Autodesk Fusion 360 part; units mm, degrees
(part 5 of 18)
  line L2716 (109.469, -153.766) -> (109.882, -153.353)
  line L2717 (144.42, -71.6049) -> (143.99, -72.0008)
  line L2718 (107.344, -63.166) -> (107.232, -63.7491)
  line L2719 (123.304, -154.504) -> (123.641, -154.981)
  line L2720 (34.8557, -118.401) -> (35.2286, -117.939)
  line L2721 (35.2286, -117.939) -> (35.57, -117.453)
  line L2722 (19.3443, -86.866) -> (19.232, -87.4491)
  line L2723 (69.1318, -73.6069) -> (69.6987, -73.7835)
  line L2724 (37.0318, -88.85) -> (37.0121, -88.2565)
  line L2725 (19.7392, -92.1175) -> (19.9741, -92.6629)
  line L2726 (71.4521, -74.0832) -> (72.0455, -74.1049)
  line L2727 (36.9725, -89.8793) -> (37.0211, -89.2874)
  line L2728 (19.1297, -89.225) -> (19.1742, -89.8171)
  line L2729 (65.8816, -58.5528) -> (66.3203, -58.1668)
  line L2730 (63.3803, -67.2861) -> (63.541, -67.8577)
  line L2731 (80.6591, -62.2784) -> (80.8266, -62.8382)
  line L2732 (19.495, -86.2917) -> (19.3443, -86.866)
  line L2733 (63.1589, -63.6096) -> (63.2769, -63.0373)
  line L2734 (23.5183, -96.5579) -> (24.0392, -96.8431)
  line L2735 (66.3203, -58.1668) -> (66.7829, -57.8099)
  line L2736 (63.078, -64.1883) -> (63.1589, -63.6096)
  line L2737 (37.0121, -88.2565) -> (36.9531, -87.6656)
  line L2738 (69.2202, -73.7373) -> (68.672, -73.5351)
  line L2739 (63.2769, -63.0373) -> (63.4315, -62.4738)
  line L2740 (24.5778, -97.0931) -> (25.1318, -97.3069)
  line L2741 (64.7274, -59.869) -> (65.0836, -59.4057)
  line L2742 (23.0175, -96.2389) -> (23.5183, -96.5579)
  line L2743 (70.35, -74.0337) -> (69.7803, -73.9038)
  line L2744 (76.5607, -73.0111) -> (76.0441, -73.2841)
  line L2745 (19.6834, -85.7285) -> (19.495, -86.2917)
  line L2746 (76.1995, -57.0936) -> (76.7108, -57.3764)
  line L2747 (78.8234, -71.1821) -> (78.42, -71.6049)
  line L2748 (72.6766, -74.1801) -> (72.0926, -74.2)
  line L2749 (64.3113, -69.7975) -> (64.0276, -69.2867)
  line L2750 (67.5183, -72.8579) -> (68.0392, -73.1431)
  line L2751 (36.7185, -86.5021) -> (36.5439, -85.9345)
  line L2752 (80.6024, -68.1858) -> (80.3887, -68.7297)
  line L2753 (20.8876, -94.1892) -> (21.2572, -94.6539)
  line L2754 (36.5439, -85.9345) -> (36.3321, -85.3798)
  line L2755 (33.0844, -96.274) -> (33.5654, -95.9258)
  line L2756 (30.3945, -97.4999) -> (30.9627, -97.3272)
  line L2757 (65.0836, -59.4057) -> (65.4688, -58.9664)
  line L2758 (19.3817, -91.3597) -> (19.2379, -90.7934)
  line L2759 (35.2286, -94.2393) -> (35.57, -93.7534)
  line L2760 (23.3845, -81.2228) -> (22.8893, -81.5505)
  line L2761 (79.8585, -69.7704) -> (79.5441, -70.263)
  line L2762 (25.5484, -80.2593) -> (24.9847, -80.4458)
  line L2763 (25.1318, -97.3069) -> (25.6987, -97.4835)
  line L2764 (81.0514, -63.9844) -> (81.1079, -64.566)
  line L2765 (81.1251, -65.3237) -> (81.0951, -65.9073)
  line L2766 (22.8893, -81.5505) -> (22.417, -81.9104)
  line L2767 (80.7806, -67.6293) -> (80.6024, -68.1858)
  line L2768 (68.138, -73.2979) -> (67.6204, -73.0267)
  line L2769 (68.8336, -56.7011) -> (69.3856, -56.5094)
  line L2770 (67.1214, -72.7227) -> (66.643, -72.3871)
  line L2771 (64.402, -60.3542) -> (64.7274, -59.869)
  line L2772 (63.7774, -68.7587) -> (63.5618, -68.2156)
  line L2773 (64.9746, -70.759) -> (64.6274, -70.289)
  line L2774 (63.1742, -66.1171) -> (63.2578, -66.705)
  line L2775 (64.0276, -69.2867) -> (63.7774, -68.7587)
  line L2776 (69.9488, -56.3538) -> (70.5208, -56.2348)
  line L2777 (63.3817, -67.6597) -> (63.2379, -67.0934)
  line L2778 (80.3887, -68.7297) -> (80.1404, -69.2586)
  line L2779 (20.17, -84.6459) -> (19.9088, -85.1791)
  line L2780 (79.3045, -59.7036) -> (79.6409, -60.1813)
  line L2781 (26.2761, -97.6221) -> (26.8615, -97.7221)
  line L2782 (32.0585, -96.8711) -> (32.5813, -96.5896)
  line L2783 (32.5813, -96.5896) -> (33.0844, -96.274)
  line L2784 (27.8893, -79.897) -> (27.2963, -79.9291)
  line L2785 (80.8266, -62.8382) -> (80.9575, -63.4077)
  line L2786 (21.9695, -82.3007) -> (21.5489, -82.7199)
  line L2787 (72.2663, -56.102) -> (72.8498, -56.1331)
  line L2788 (63.9741, -68.9629) -> (64.2446, -69.4915)
  line L2789 (19.2379, -90.7934) -> (19.1309, -90.2189)
  line L2790 (20.6274, -93.989) -> (20.3113, -93.4975)
  line L2791 (19.0332, -88.6312) -> (19.0347, -88.471)
  line L2792 (66.7829, -57.8099) -> (67.2676, -57.4835)
  line L2793 (79.1986, -70.7342) -> (78.8234, -71.1821)
  line L2794 (19.2578, -90.405) -> (19.3803, -90.9861)
  line L2795 (65.6569, -71.3931) -> (66.0847, -71.8049)
  line L2796 (36.5935, -91.6172) -> (36.7582, -91.0467)
  line L2797 (19.0291, -89.0553) -> (19.0332, -88.6312)
  line L2798 (31.9179, -80.7606) -> (31.3734, -80.5239)
  line L2799 (65.4688, -58.9664) -> (65.8816, -58.5528)
  line L2800 (33.9045, -82.0507) -> (33.4411, -81.6795)
  line L2801 (68.2951, -56.928) -> (68.8336, -56.7011)
  line L2802 (27.4521, -97.7832) -> (28.0455, -97.8049)
  line L2803 (72.0455, -74.1049) -> (72.6391, -74.0873)
  line L2804 (36.8551, -87.08) -> (36.7185, -86.5021)
  line L2805 (71.5085, -74.1821) -> (70.9269, -74.1266)
  line L2806 (77.9903, -72.0008) -> (77.5358, -72.3681)
  line L2807 (22.417, -81.9104) -> (21.9695, -82.3007)
  line L2808 (34.7525, -82.8812) -> (34.3423, -82.4519)
  line L2809 (69.3856, -56.5094) -> (69.9488, -56.3538)
  line L2810 (63.1309, -66.5189) -> (63.0612, -65.9388)
  line L2811 (73.4301, -56.2018) -> (74.0047, -56.3077)
  line L2812 (20.0276, -92.9867) -> (19.7774, -92.4587)
  line L2813 (19.1742, -89.8171) -> (19.2578, -90.405)
  line L2814 (20.5495, -93.701) -> (20.8876, -94.1892)
  line L2815 (19.3803, -90.9861) -> (19.541, -91.5577)
  line L2816 (73.2581, -74.1226) -> (72.6766, -74.1801)
  line L2817 (36.9531, -87.6656) -> (36.8551, -87.08)
  line L2818 (63.2578, -66.705) -> (63.3803, -67.2861)
  line L2819 (21.5489, -82.7199) -> (21.157, -83.166)
  line L2820 (37.0211, -89.2874) -> (37.0318, -88.85)
  line L2821 (80.4559, -61.7305) -> (80.6591, -62.2784)
  line L2822 (75.5109, -73.5231) -> (74.9634, -73.7273)
  line L2823 (77.6734, -58.038) -> (78.1207, -58.414)
  line L2824 (34.3423, -82.4519) -> (33.9045, -82.0507)
  line L2825 (31.3734, -80.5239) -> (30.8143, -80.3237)
  line L2826 (32.4456, -81.033) -> (31.9179, -80.7606)
  line L2827 (22.539, -95.8873) -> (23.0175, -96.2389)
  line L2828 (29.075, -79.9508) -> (28.483, -79.9042)
  line L2829 (77.5358, -72.3681) -> (77.0587, -72.7054)
  line L2830 (63.0612, -65.9388) -> (63.0291, -65.3553)
  line L2831 (35.8785, -93.246) -> (36.1527, -92.7193)
  line L2832 (69.6987, -73.7835) -> (70.2761, -73.9221)
  line L2833 (63.6222, -61.9215) -> (63.8482, -61.3827)
  line L2834 (29.2302, -97.7304) -> (29.8162, -97.6345)
  line L2835 (26.7068, -80.0004) -> (26.1233, -80.1107)
  line L2836 (36.3321, -85.3798) -> (36.084, -84.8403)
  line L2837 (35.1334, -83.3368) -> (34.7525, -82.8812)
  line L2838 (64.6274, -70.289) -> (64.3113, -69.7975)
  line L2839 (66.0847, -71.8049) -> (66.539, -72.1873)
  line L2840 (74.0047, -56.3077) -> (74.5713, -56.4506)
  line L2841 (66.1873, -72.0214) -> (65.7561, -71.627)
  line L2842 (36.8847, -90.4665) -> (36.9725, -89.8793)
  line L2843 (80.9575, -63.4077) -> (81.0514, -63.9844)
  line L2844 (79.6409, -60.1813) -> (79.9457, -60.6798)
  line L2845 (67.6204, -73.0267) -> (67.1214, -72.7227)
  line L2846 (23.9003, -80.9286) -> (23.3845, -81.2228)
  line L2847 (36.3914, -92.1756) -> (36.5935, -91.6172)
  line L2848 (64.5495, -70.001) -> (64.8876, -70.4892)
  line L2849 (71.682, -56.1086) -> (72.2663, -56.102)
  line L2850 (78.5428, -58.818) -> (78.9379, -59.2485)
  line L2851 (66.643, -72.3871) -> (66.1873, -72.0214)
  line L2852 (33.4411, -81.6795) -> (32.954, -81.3397)
  line L2853 (19.9741, -92.6629) -> (20.2446, -93.1915)
  line L2854 (74.4039, -73.8957) -> (73.8346, -74.0276)
  line L2855 (36.1527, -92.7193) -> (36.3914, -92.1756)
  line L2856 (28.6391, -97.7873) -> (29.2302, -97.7304)
  line L2857 (74.5713, -56.4506) -> (75.1275, -56.6297)
  line L2858 (19.0612, -89.6388) -> (19.0291, -89.0553)
  line L2859 (72.8498, -56.1331) -> (73.4301, -56.2018)
  line L2860 (32.954, -81.3397) -> (32.4456, -81.033)
  line L2861 (73.8346, -74.0276) -> (73.2581, -74.1226)
  line L2862 (70.9269, -74.1266) -> (70.35, -74.0337)
  line L2863 (35.57, -93.7534) -> (35.8785, -93.246)
  line L2864 (71.0994, -56.1529) -> (71.682, -56.1086)
  line L2865 (63.5618, -68.2156) -> (63.3817, -67.6597)
  line L2866 (20.3113, -93.4975) -> (20.0276, -92.9867)
  line L2867 (69.7803, -73.9038) -> (69.2202, -73.7373)
  line L2868 (19.7774, -92.4587) -> (19.5618, -91.9156)
  line L2869 (19.232, -87.4491) -> (19.1587, -88.0384)
  line L2870 (30.8143, -80.3237) -> (30.2432, -80.161)
  line L2871 (65.7561, -71.627) -> (65.3513, -71.2056)
  line L2872 (80.9224, -67.0625) -> (80.7806, -67.6293)
  line L2873 (81.1079, -64.566) -> (81.1268, -65.15)
  line L2874 (63.0347, -64.771) -> (63.078, -64.1883)
  line L2875 (24.0392, -96.8431) -> (24.5778, -97.0931)
  line L2876 (75.1275, -56.6297) -> (75.671, -56.8443)
  line L2877 (35.8006, -84.3185) -> (35.4833, -83.8165)
  line L2878 (26.1233, -80.1107) -> (25.5484, -80.2593)
  line L2879 (19.541, -91.5577) -> (19.7392, -92.1175)
  line L2880 (79.9457, -60.6798) -> (80.2178, -61.1969)
  line L2881 (29.8162, -97.6345) -> (30.3945, -97.4999)
  line L2882 (36.084, -84.8403) -> (35.8006, -84.3185)
  line L2883 (35.4833, -83.8165) -> (35.1334, -83.3368)
  line L2884 (68.5778, -73.3931) -> (69.1318, -73.6069)
  line L2885 (81.1268, -65.15) -> (81.1251, -65.3237)
  line L2886 (63.0291, -65.3553) -> (63.0332, -64.9312)
  line L2887 (19.1245, -88.6312) -> (19.1297, -89.225)
  line L2888 (78.1207, -58.414) -> (78.5428, -58.818)
  line L2889 (28.483, -79.9042) -> (27.8893, -79.897)
  line L2890 (19.1587, -88.0384) -> (19.1245, -88.6312)
  line L2891 (80.2178, -61.1969) -> (80.4559, -61.7305)
  line L2892 (72.0926, -74.2) -> (71.5085, -74.1821)
  line L2893 (67.7724, -57.1892) -> (68.2951, -56.928)
  line L2894 (64.2446, -69.4915) -> (64.5495, -70.001)
  line L2895 (24.9847, -80.4458) -> (24.4345, -80.6692)
  line L2896 (25.6987, -97.4835) -> (26.2761, -97.6221)
  line L2897 (63.8482, -61.3827) -> (64.1085, -60.8595)
  line L2898 (70.8615, -74.0221) -> (71.4521, -74.0832)
  line L2899 (65.2572, -70.9539) -> (65.6569, -71.3931)
  line L2900 (65.3513, -71.2056) -> (64.9746, -70.759)
  line L2901 (24.4345, -80.6692) -> (23.9003, -80.9286)
  line L2902 (78.9379, -59.2485) -> (79.3045, -59.7036)
  line L2903 (29.6626, -80.0365) -> (29.075, -79.9508)
  line L2904 (68.0392, -73.1431) -> (68.5778, -73.3931)
  line L2905 (77.2028, -57.6917) -> (77.6734, -58.038)
  line L2906 (81.0951, -65.9073) -> (81.0274, -66.4877)
  line L2907 (28.0455, -97.8049) -> (28.6391, -97.7873)
  line L2908 (74.9634, -73.7273) -> (74.4039, -73.8957)
  line L2909 (64.1085, -60.8595) -> (64.402, -60.3542)
  line L2910 (19.0347, -88.471) -> (19.078, -87.8883)
  line L2911 (66.539, -72.1873) -> (67.0175, -72.5389)
  line L2912 (27.2963, -79.9291) -> (26.7068, -80.0004)
  line L2913 (22.0847, -95.5049) -> (22.539, -95.8873)
  line L2914 (20.7955, -83.6371) -> (20.466, -84.1311)
  line L2915 (34.0223, -95.5465) -> (34.453, -95.1378)
  line L2916 (68.672, -73.5351) -> (68.138, -73.2979)
  line L2917 (67.2676, -57.4835) -> (67.7724, -57.1892)
  line L2918 (63.2379, -67.0934) -> (63.1309, -66.5189)
  line L2919 (63.4315, -62.4738) -> (63.6222, -61.9215)
  line L2920 (63.7392, -68.4175) -> (63.9741, -68.9629)
  line L2921 (63.541, -67.8577) -> (63.7392, -68.4175)
  line L2922 (67.0175, -72.5389) -> (67.5183, -72.8579)
  line L2923 (64.8876, -70.4892) -> (65.2572, -70.9539)
  line L2924 (34.453, -95.1378) -> (34.8557, -94.7014)
  line L2925 (19.5618, -91.9156) -> (19.3817, -91.3597)
  line L2926 (70.2761, -73.9221) -> (70.8615, -74.0221)
  line L2927 (78.42, -71.6049) -> (77.9903, -72.0008)
  line L2928 (34.8557, -94.7014) -> (35.2286, -94.2393)
  line L2929 (79.5441, -70.263) -> (79.1986, -70.7342)
  line L2930 (36.7582, -91.0467) -> (36.8847, -90.4665)
  line L2931 (26.8615, -97.7221) -> (27.4521, -97.7832)
  line L2932 (21.6569, -95.0931) -> (22.0847, -95.5049)
  line L2933 (21.2572, -94.6539) -> (21.6569, -95.0931)
  line L2934 (76.7108, -57.3764) -> (77.2028, -57.6917)
  line L2935 (30.9627, -97.3272) -> (31.5182, -97.1173)
  line L2936 (75.671, -56.8443) -> (76.1995, -57.0936)
  line L2937 (30.2432, -80.161) -> (29.6626, -80.0365)
  line L2938 (19.1309, -90.2189) -> (19.0612, -89.6388)
  line L2939 (63.0332, -64.9312) -> (63.0347, -64.771)
  line L2940 (20.2446, -93.1915) -> (20.5495, -93.701)
  line L2941 (20.466, -84.1311) -> (20.17, -84.6459)
  line L2942 (20.9746, -94.459) -> (20.6274, -93.989)
  line L2943 (70.5208, -56.2348) -> (71.0994, -56.1529)
  line L2944 (81.0274, -66.4877) -> (80.9224, -67.0625)
  line L2945 (76.0441, -73.2841) -> (75.5109, -73.5231)
  line L2946 (33.5654, -95.9258) -> (34.0223, -95.5465)
  line L2947 (19.9088, -85.1791) -> (19.6834, -85.7285)
  line L2948 (31.5182, -97.1173) -> (32.0585, -96.8711)
  line L2949 (21.157, -83.166) -> (20.7955, -83.6371)
  line L2950 (80.1404, -69.2586) -> (79.8585, -69.7704)
  line L2951 (77.0587, -72.7054) -> (76.5607, -73.0111)
  line L2952 (191.027, -66.4877) -> (190.922, -67.0625)
  line L2953 (190.922, -67.0625) -> (190.781, -67.6293)
  line L2954 (191.125, -65.3237) -> (191.095, -65.9073)
  line L2955 (153.257, -70.9539) -> (153.657, -71.3931)
  line L2956 (154.539, -72.1873) -> (155.018, -72.5389)
  line L2957 (154.085, -71.8049) -> (154.539, -72.1873)
  line L2958 (155.518, -72.8579) -> (156.039, -73.1431)
  line L2959 (173.131, -66.5189) -> (173.061, -65.9388)
  line L2960 (173.061, -65.9388) -> (173.029, -65.3553)
  line L2961 (173.909, -61.4791) -> (173.683, -62.0285)
  line L2962 (173.344, -63.166) -> (173.232, -63.7491)
  line L2963 (173.495, -62.5917) -> (173.344, -63.166)
  line L2964 (173.13, -65.525) -> (173.174, -66.1171)
  line L2965 (173.232, -63.7491) -> (173.159, -64.3384)
  line L2966 (173.159, -64.3384) -> (173.124, -64.9312)
  line L2967 (151.258, -66.705) -> (151.38, -67.2861)
  line L2968 (151.739, -68.4175) -> (151.974, -68.9629)
  line L2969 (151.541, -67.8577) -> (151.739, -68.4175)
  line L2970 (152.245, -69.4915) -> (152.55, -70.001)
  line L2971 (173.124, -64.9312) -> (173.13, -65.525)
  line L2972 (151.078, -64.1883) -> (151.159, -63.6096)
  line L2973 (151.159, -63.6096) -> (151.277, -63.0373)
  line L2974 (151.432, -62.4738) -> (151.622, -61.9215)
  line L2975 (161.075, -56.2508) -> (160.483, -56.2042)
  line L2976 (163.918, -57.0606) -> (163.373, -56.8239)
  line L2977 (63.9088, -61.4791) -> (63.6834, -62.0285)
  line L2978 (162.814, -56.6237) -> (162.243, -56.461)
  line L2979 (163.373, -56.8239) -> (162.814, -56.6237)
  line L2980 (161.663, -56.3365) -> (161.075, -56.2508)
  line L2981 (176.417, -58.2104) -> (175.97, -58.6007)
  line L2982 (80.8847, -66.7665) -> (80.9725, -66.1793)
  line L2983 (63.6834, -62.0285) -> (63.495, -62.5917)
  line L2984 (64.466, -60.4311) -> (64.17, -60.9459)
  line L2985 (80.9725, -66.1793) -> (81.0211, -65.5875)
  line L2986 (191.095, -65.9073) -> (191.027, -66.4877)
  line L2987 (79.1334, -59.6368) -> (78.7525, -59.1812)
  line L2988 (191.108, -64.566) -> (191.127, -65.15)
  line L2989 (173.238, -67.0934) -> (173.131, -66.5189)
  line L2990 (173.382, -67.6597) -> (173.238, -67.0934)
  line L2991 (191.127, -65.15) -> (191.125, -65.3237)
  line L2992 (190.957, -63.4077) -> (191.051, -63.9844)
  line L2993 (191.051, -63.9844) -> (191.108, -64.566)
  line L2994 (151.974, -68.9629) -> (152.245, -69.4915)
  line L2995 (152.888, -70.4892) -> (153.257, -70.9539)
  line L2996 (152.55, -70.001) -> (152.888, -70.4892)
  line L2997 (153.657, -71.3931) -> (154.085, -71.8049)
  line L2998 (173.777, -68.7587) -> (173.562, -68.2156)
  line L2999 (173.562, -68.2156) -> (173.382, -67.6597)
  line L3000 (176.889, -57.8505) -> (176.417, -58.2104)
  line L3001 (175.549, -59.0199) -> (175.157, -59.466)
  line L3002 (175.97, -58.6007) -> (175.549, -59.0199)
  line L3003 (174.17, -60.9459) -> (173.909, -61.4791)
  line L3004 (175.157, -59.466) -> (174.795, -59.9371)
  line L3005 (174.795, -59.9371) -> (174.466, -60.4311)
  line L3006 (151.382, -67.6597) -> (151.238, -67.0934)
  line L3007 (151.061, -65.9388) -> (151.029, -65.3553)
  line L3008 (151.131, -66.5189) -> (151.061, -65.9388)
  line L3009 (151.033, -64.9312) -> (151.035, -64.771)
  line L3010 (174.466, -60.4311) -> (174.17, -60.9459)
  line L3011 (151.277, -63.0373) -> (151.432, -62.4738)
  line L3012 (173.683, -62.0285) -> (173.495, -62.5917)
  line L3013 (151.848, -61.3827) -> (152.108, -60.8595)
  line L3014 (164.954, -57.6397) -> (164.446, -57.333)
  line L3015 (165.441, -57.9794) -> (164.954, -57.6397)
  line L3016 (64.17, -60.9459) -> (63.9088, -61.4791)
  line L3017 (164.446, -57.333) -> (163.918, -57.0606)
  line L3018 (166.753, -59.1812) -> (166.342, -58.7519)
  line L3019 (162.243, -56.461) -> (161.663, -56.3365)
  line L3020 (182.483, -56.2042) -> (181.889, -56.197)
  line L3021 (80.5935, -67.9172) -> (80.7582, -67.3467)
  line L3022 (65.157, -59.466) -> (64.7955, -59.9371)
  line L3023 (64.7955, -59.9371) -> (64.466, -60.4311)
  line L3024 (80.7582, -67.3467) -> (80.8847, -66.7665)
  line L3025 (190.659, -62.2784) -> (190.827, -62.8382)
  line L3026 (80.084, -61.1403) -> (79.8006, -60.6185)
  line L3027 (190.827, -62.8382) -> (190.957, -63.4077)
  line L3028 (174.028, -69.2867) -> (173.777, -68.7587)
  line L3029 (174.311, -69.7975) -> (174.028, -69.2867)
  line L3030 (190.218, -61.1969) -> (190.456, -61.7305)
  line L3031 (190.456, -61.7305) -> (190.659, -62.2784)
  line L3032 (189.641, -60.1813) -> (189.946, -60.6798)
  line L3033 (151.029, -65.3553) -> (151.033, -64.9312)
  line L3034 (151.174, -66.1171) -> (151.258, -66.705)
  line L3035 (151.035, -64.771) -> (151.078, -64.1883)
  line L3036 (151.38, -67.2861) -> (151.541, -67.8577)
  line L3037 (174.975, -70.759) -> (174.627, -70.289)
  line L3038 (174.627, -70.289) -> (174.311, -69.7975)
  line L3039 (180.707, -56.3004) -> (180.123, -56.4107)
  line L3040 (181.296, -56.2291) -> (180.707, -56.3004)
  line L3041 (179.548, -56.5593) -> (178.985, -56.7458)
  line L3042 (178.985, -56.7458) -> (178.434, -56.9692)
  line L3043 (178.434, -56.9692) -> (177.9, -57.2286)
  line L3044 (180.123, -56.4107) -> (179.548, -56.5593)
  line L3045 (153.756, -71.627) -> (153.351, -71.2056)
  line L3046 (152.627, -70.289) -> (152.311, -69.7975)
  line L3047 (152.975, -70.759) -> (152.627, -70.289)
  line L3048 (152.028, -69.2867) -> (151.777, -68.7587)
  line L3049 (177.385, -57.5228) -> (176.889, -57.8505)
  line L3050 (151.622, -61.9215) -> (151.848, -61.3827)
  line L3051 (177.9, -57.2286) -> (177.385, -57.5228)
  line L3052 (152.402, -60.3542) -> (152.727, -59.869)
  line L3053 (166.342, -58.7519) -> (165.904, -58.3507)
  line L3054 (168.084, -61.1403) -> (167.801, -60.6185)
  line L3055 (65.9695, -58.6007) -> (65.5489, -59.0199)
  line L3056 (167.483, -60.1165) -> (167.133, -59.6368)
  line L3057 (167.801, -60.6185) -> (167.483, -60.1165)
  line L3058 (165.904, -58.3507) -> (165.441, -57.9794)
  line L3059 (186.446, -57.333) -> (185.918, -57.0606)
  line L3060 (80.1527, -69.0193) -> (80.3914, -68.4756)
  line L3061 (65.5489, -59.0199) -> (65.157, -59.466)
  line L3062 (66.8893, -57.8505) -> (66.417, -58.2104)
  line L3063 (80.3914, -68.4756) -> (80.5935, -67.9172)
  line L3064 (189.946, -60.6798) -> (190.218, -61.1969)
  line L3065 (79.8006, -60.6185) -> (79.4833, -60.1165)
  line L3066 (188.938, -59.2485) -> (189.304, -59.7036)
  line L3067 (175.351, -71.2056) -> (174.975, -70.759)
  line L3068 (175.756, -71.627) -> (175.351, -71.2056)
  line L3069 (189.304, -59.7036) -> (189.641, -60.1813)
  line L3070 (188.121, -58.414) -> (188.543, -58.818)
  line L3071 (188.543, -58.818) -> (188.938, -59.2485)
  line L3072 (152.311, -69.7975) -> (152.028, -69.2867)
  line L3073 (151.562, -68.2156) -> (151.382, -67.6597)
  line L3074 (151.777, -68.7587) -> (151.562, -68.2156)
  line L3075 (151.238, -67.0934) -> (151.131, -66.5189)
  line L3076 (176.643, -72.3871) -> (176.187, -72.0214)
  line L3077 (176.187, -72.0214) -> (175.756, -71.627)
  line L3078 (186.954, -57.6397) -> (186.446, -57.333)
  line L3079 (185.373, -56.8239) -> (184.814, -56.6237)
  line L3080 (185.918, -57.0606) -> (185.373, -56.8239)
  line L3081 (183.075, -56.2508) -> (182.483, -56.2042)
  line L3082 (184.814, -56.6237) -> (184.243, -56.461)
  line L3083 (184.243, -56.461) -> (183.663, -56.3365)
  line L3084 (157.78, -73.9038) -> (157.22, -73.7373)
  line L3085 (156.138, -73.2979) -> (155.62, -73.0267)
  line L3086 (156.672, -73.5351) -> (156.138, -73.2979)
  line L3087 (155.121, -72.7227) -> (154.643, -72.3871)
  line L3088 (183.663, -56.3365) -> (183.075, -56.2508)
  line L3089 (152.108, -60.8595) -> (152.402, -60.3542)
  line L3090 (181.889, -56.197) -> (181.296, -56.2291)
  line L3091 (153.084, -59.4057) -> (153.469, -58.9664)
  line L3092 (168.544, -62.2345) -> (168.332, -61.6798)
  line L3093 (168.719, -62.8021) -> (168.544, -62.2345)
  line L3094 (66.417, -58.2104) -> (65.9695, -58.6007)
  line L3095 (168.332, -61.6798) -> (168.084, -61.1403)
  line L3096 (169.012, -64.5565) -> (168.953, -63.9656)
  line L3097 (167.133, -59.6368) -> (166.753, -59.1812)
  line L3098 (190.544, -62.2345) -> (190.332, -61.6798)
  line L3099 (79.57, -70.0534) -> (79.8785, -69.546)
  line L3100 (67.9003, -57.2286) -> (67.3845, -57.5228)
  line L3101 (67.3845, -57.5228) -> (66.8893, -57.8505)
  line L3102 (79.8785, -69.546) -> (80.1527, -69.0193)
  line L3103 (187.203, -57.6917) -> (187.673, -58.038)
  line L3104 (80.5439, -62.2345) -> (80.3321, -61.6798)
  line L3105 (187.673, -58.038) -> (188.121, -58.414)
  line L3106 (177.121, -72.7227) -> (176.643, -72.3871)
  line L3107 (177.62, -73.0267) -> (177.121, -72.7227)
  line L3108 (186.199, -57.0936) -> (186.711, -57.3764)
  line L3109 (186.711, -57.3764) -> (187.203, -57.6917)
  line L3110 (185.128, -56.6297) -> (185.671, -56.8443)
  line L3111 (155.62, -73.0267) -> (155.121, -72.7227)
  line L3112 (154.187, -72.0214) -> (153.756, -71.627)
  line L3113 (154.643, -72.3871) -> (154.187, -72.0214)
  line L3114 (153.351, -71.2056) -> (152.975, -70.759)
  line L3115 (178.672, -73.5351) -> (178.138, -73.2979)
  line L3116 (178.138, -73.2979) -> (177.62, -73.0267)
  line L3117 (189.801, -60.6185) -> (189.483, -60.1165)
  line L3118 (190.084, -61.1403) -> (189.801, -60.6185)
  line L3119 (189.133, -59.6368) -> (188.753, -59.1812)
  line L3120 (188.753, -59.1812) -> (188.342, -58.7519)
  line L3121 (188.342, -58.7519) -> (187.904, -58.3507)
  line L3122 (189.483, -60.1165) -> (189.133, -59.6368)
  line L3123 (162.404, -73.8957) -> (161.835, -74.0276)
  line L3124 (160.677, -74.1801) -> (160.093, -74.2)
  line L3125 (161.258, -74.1226) -> (160.677, -74.1801)
  line L3126 (159.509, -74.1821) -> (158.927, -74.1266)
  line L3127 (187.441, -57.9794) -> (186.954, -57.6397)
  line L3128 (152.727, -59.869) -> (153.084, -59.4057)
  line L3129 (187.904, -58.3507) -> (187.441, -57.9794)
  line L3130 (153.882, -58.5528) -> (154.32, -58.1668)
  line L3131 (168.953, -63.9656) -> (168.855, -63.38)
  line L3132 (168.885, -66.7665) -> (168.972, -66.1793)
  line L3133 (68.9847, -56.7458) -> (68.4345, -56.9692)
  line L3134 (169.021, -65.5875) -> (169.032, -65.15)
  line L3135 (168.972, -66.1793) -> (169.021, -65.5875)
  line L3136 (168.855, -63.38) -> (168.719, -62.8021)
  line L3137 (190.972, -66.1793) -> (191.021, -65.5875)
  line L3138 (78.8557, -71.0014) -> (79.2286, -70.5393)
  line L3139 (68.4345, -56.9692) -> (67.9003, -57.2286)
  line L3140 (70.1233, -56.4107) -> (69.5484, -56.5593)
  line L3141 (79.2286, -70.5393) -> (79.57, -70.0534)
  line L3142 (185.671, -56.8443) -> (186.199, -57.0936)
  line L3143 (80.3321, -61.6798) -> (80.084, -61.1403)
  line L3144 (184.005, -56.3077) -> (184.571, -56.4506)
  line L3145 (179.22, -73.7373) -> (178.672, -73.5351)
  line L3146 (179.78, -73.9038) -> (179.22, -73.7373)
  line L3147 (184.571, -56.4506) -> (185.128, -56.6297)
  line L3148 (182.85, -56.1331) -> (183.43, -56.2018)
  line L3149 (183.43, -56.2018) -> (184.005, -56.3077)
  line L3150 (160.093, -74.2) -> (159.509, -74.1821)
  line L3151 (158.35, -74.0337) -> (157.78, -73.9038)
  line L3152 (158.927, -74.1266) -> (158.35, -74.0337)
  line L3153 (157.22, -73.7373) -> (156.672, -73.5351)
  line L3154 (180.927, -74.1266) -> (180.35, -74.0337)
  line L3155 (180.35, -74.0337) -> (179.78, -73.9038)
  line L3156 (190.885, -66.7665) -> (190.972, -66.1793)
  line L3157 (191.032, -65.15) -> (191.012, -64.5565)
  line L3158 (191.021, -65.5875) -> (191.032, -65.15)
  line L3159 (190.719, -62.8021) -> (190.544, -62.2345)
  line L3160 (191.012, -64.5565) -> (190.953, -63.9656)
  line L3161 (190.953, -63.9656) -> (190.855, -63.38)
  line L3162 (166.42, -71.6049) -> (165.99, -72.0008)
  line L3163 (165.059, -72.7054) -> (164.561, -73.0111)
  line L3164 (165.536, -72.3681) -> (165.059, -72.7054)
  line L3165 (164.044, -73.2841) -> (163.511, -73.5231)
  line L3166 (190.855, -63.38) -> (190.719, -62.8021)
  line L3167 (153.469, -58.9664) -> (153.882, -58.5528)
  line L3168 (190.332, -61.6798) -> (190.084, -61.1403)
  line L3169 (154.783, -57.8099) -> (155.268, -57.4835)
  line L3170 (168.594, -67.9172) -> (168.758, -67.3467)
  line L3171 (168.391, -68.4756) -> (168.594, -67.9172)
  line L3172 (69.5484, -56.5593) -> (68.9847, -56.7458)
  line L3173 (168.758, -67.3467) -> (168.885, -66.7665)
  line L3174 (167.57, -70.0534) -> (167.879, -69.546)
  line L3175 (169.032, -65.15) -> (169.012, -64.5565)
  line L3176 (188.022, -71.8465) -> (188.453, -71.4378)
  line L3177 (78.0223, -71.8465) -> (78.453, -71.4378)
  line L3178 (71.2963, -56.2291) -> (70.7068, -56.3004)
  line L3179 (70.7068, -56.3004) -> (70.1233, -56.4107)
  line L3180 (78.453, -71.4378) -> (78.8557, -71.0014)
  line L3181 (181.682, -56.1086) -> (182.266, -56.102)
  line L3182 (80.8551, -63.38) -> (80.7185, -62.8021)
  line L3183 (182.266, -56.102) -> (182.85, -56.1331)
  line L3184 (181.509, -74.1821) -> (180.927, -74.1266)
  line L3185 (182.093, -74.2) -> (181.509, -74.1821)
  line L3186 (180.521, -56.2348) -> (181.099, -56.1529)
  line L3187 (181.099, -56.1529) -> (181.682, -56.1086)
  line L3188 (179.386, -56.5094) -> (179.949, -56.3538)
  line L3189 (164.561, -73.0111) -> (164.044, -73.2841)
  line L3190 (162.963, -73.7273) -> (162.404, -73.8957)
  line L3191 (163.511, -73.5231) -> (162.963, -73.7273)
  line L3192 (161.835, -74.0276) -> (161.258, -74.1226)
  line L3193 (183.258, -74.1226) -> (182.677, -74.1801)
  line L3194 (182.677, -74.1801) -> (182.093, -74.2)
  line L3195 (189.229, -70.5393) -> (189.57, -70.0534)
  line L3196 (188.856, -71.0014) -> (189.229, -70.5393)
  line L3197 (189.879, -69.546) -> (190.153, -69.0193)
  line L3198 (190.153, -69.0193) -> (190.391, -68.4756)
  line L3199 (190.391, -68.4756) -> (190.594, -67.9172)
  line L3200 (189.57, -70.0534) -> (189.879, -69.546)
  line L3201 (168.781, -67.6293) -> (168.602, -68.1858)
  line L3202 (168.14, -69.2586) -> (167.858, -69.7704)
  line L3203 (168.389, -68.7297) -> (168.14, -69.2586)
  line L3204 (167.544, -70.263) -> (167.199, -70.7342)
  line L3205 (190.758, -67.3467) -> (190.885, -66.7665)
  line L3206 (154.32, -58.1668) -> (154.783, -57.8099)
  line L3207 (190.594, -67.9172) -> (190.758, -67.3467)
  line L3208 (155.772, -57.1892) -> (156.295, -56.928)
  line L3209 (167.879, -69.546) -> (168.153, -69.0193)
  line L3210 (166.022, -71.8465) -> (166.453, -71.4378)
  line L3211 (72.483, -56.2042) -> (71.8893, -56.197)
  line L3212 (166.856, -71.0014) -> (167.229, -70.5393)
  line L3213 (166.453, -71.4378) -> (166.856, -71.0014)
  line L3214 (168.153, -69.0193) -> (168.391, -68.4756)
  line L3215 (184.395, -73.7999) -> (184.963, -73.6272)
  line L3216 (77.0844, -72.574) -> (77.5654, -72.2258)
  line L3217 (71.8893, -56.197) -> (71.2963, -56.2291)
  line L3218 (73.6626, -56.3365) -> (73.075, -56.2508)
  line L3219 (77.5654, -72.2258) -> (78.0223, -71.8465)
  line L3220 (179.949, -56.3538) -> (180.521, -56.2348)
  line L3221 (80.7185, -62.8021) -> (80.5439, -62.2345)
  line L3222 (178.295, -56.928) -> (178.834, -56.7011)
  line L3223 (183.835, -74.0276) -> (183.258, -74.1226)
  line L3224 (184.404, -73.8957) -> (183.835, -74.0276)
  line L3225 (178.834, -56.7011) -> (179.386, -56.5094)
  line L3226 (177.268, -57.4835) -> (177.772, -57.1892)
  line L3227 (177.772, -57.1892) -> (178.295, -56.928)
  line L3228 (167.858, -69.7704) -> (167.544, -70.263)
  line L3229 (166.823, -71.1821) -> (166.42, -71.6049)
  line L3230 (167.199, -70.7342) -> (166.823, -71.1821)
  line L3231 (165.99, -72.0008) -> (165.536, -72.3681)
  line L3232 (185.511, -73.5231) -> (184.963, -73.7273)
  line L3233 (184.963, -73.7273) -> (184.404, -73.8957)
  line L3234 (183.816, -73.9345) -> (184.395, -73.7999)
  line L3235 (185.518, -73.4173) -> (186.059, -73.1711)
  line L3236 (184.963, -73.6272) -> (185.518, -73.4173)
  line L3237 (187.565, -72.2258) -> (188.022, -71.8465)
  line L3238 (186.059, -73.1711) -> (186.581, -72.8896)
  line L3239 (186.581, -72.8896) -> (187.084, -72.574)
  line L3240 (168.957, -63.4077) -> (169.051, -63.9844)
  line L3241 (169.127, -65.15) -> (169.125, -65.3237)
  line L3242 (169.108, -64.566) -> (169.127, -65.15)
  line L3243 (169.095, -65.9073) -> (169.027, -66.4877)
  line L3244 (187.084, -72.574) -> (187.565, -72.2258)
  line L3245 (155.268, -57.4835) -> (155.772, -57.1892)
  line L3246 (188.453, -71.4378) -> (188.856, -71.0014)
  line L3247 (156.834, -56.7011) -> (157.386, -56.5094)
  line L3248 (165.084, -72.574) -> (165.565, -72.2258)
  line L3249 (164.581, -72.8896) -> (165.084, -72.574)
  line L3250 (73.075, -56.2508) -> (72.483, -56.2042)
  line L3251 (165.565, -72.2258) -> (166.022, -71.8465)
  line L3252 (162.963, -73.6272) -> (163.518, -73.4173)
  line L3253 (167.229, -70.5393) -> (167.57, -70.0534)
  line L3254 (178.039, -73.1431) -> (178.578, -73.3931)
  line L3255 (76.0585, -73.1711) -> (76.5813, -72.8896)
  line L3256 (74.8143, -56.6237) -> (74.2432, -56.461)
  line L3257 (74.2432, -56.461) -> (73.6626, -56.3365)
  line L3258 (76.5813, -72.8896) -> (77.0844, -72.574)
  line L3259 (176.32, -58.1668) -> (176.783, -57.8099)
  line L3260 (81.0121, -64.5565) -> (80.9531, -63.9656)
  line L3261 (176.783, -57.8099) -> (177.268, -57.4835)
  line L3262 (186.044, -73.2841) -> (185.511, -73.5231)
  line L3263 (186.561, -73.0111) -> (186.044, -73.2841)
  line L3264 (175.469, -58.9664) -> (175.882, -58.5528)
  line L3265 (175.882, -58.5528) -> (176.32, -58.1668)
  line L3266 (174.727, -59.869) -> (175.084, -59.4057)
  line L3267 (169.125, -65.3237) -> (169.095, -65.9073)
  line L3268 (168.922, -67.0625) -> (168.781, -67.6293)
  line L3269 (169.027, -66.4877) -> (168.922, -67.0625)
  line L3270 (168.602, -68.1858) -> (168.389, -68.7297)
  line L3271 (187.536, -72.3681) -> (187.059, -72.7054)
  line L3272 (187.059, -72.7054) -> (186.561, -73.0111)
  line L3273 (179.699, -73.7835) -> (180.276, -73.9221)
  line L3274 (179.132, -73.6069) -> (179.699, -73.7835)
  line L3275 (180.861, -74.0221) -> (181.452, -74.0832)
  line L3276 (181.452, -74.0832) -> (182.046, -74.1049)
  line L3277 (182.046, -74.1049) -> (182.639, -74.0873)
  line L3278 (180.276, -73.9221) -> (180.861, -74.0221)
  line L3279 (166.938, -59.2485) -> (167.304, -59.7036)
  line L3280 (167.946, -60.6798) -> (168.218, -61.1969)
  line L3281 (167.641, -60.1813) -> (167.946, -60.6798)
  line L3282 (168.456, -61.7305) -> (168.659, -62.2784)
  line L3283 (183.23, -74.0304) -> (183.816, -73.9345)
  line L3284 (156.295, -56.928) -> (156.834, -56.7011)
  line L3285 (182.639, -74.0873) -> (183.23, -74.0304)
  line L3286 (157.949, -56.3538) -> (158.521, -56.2348)
  line L3287 (163.518, -73.4173) -> (164.059, -73.1711)
  line L3288 (160.639, -74.0873) -> (161.23, -74.0304)
  line L3289 (75.9179, -57.0606) -> (75.3734, -56.8239)
  line L3290 (161.816, -73.9345) -> (162.395, -73.7999)
  line L3291 (161.23, -74.0304) -> (161.816, -73.9345)
  line L3292 (164.059, -73.1711) -> (164.581, -72.8896)
  line L3293 (174.888, -70.4892) -> (175.257, -70.9539)
  line L3294 (74.9627, -73.6272) -> (75.5182, -73.4173)
  line L3295 (75.3734, -56.8239) -> (74.8143, -56.6237)
  line L3296 (76.954, -57.6397) -> (76.4456, -57.333)
  line L3297 (75.5182, -73.4173) -> (76.0585, -73.1711)
  line L3298 (175.084, -59.4057) -> (175.469, -58.9664)
  line L3299 (80.9531, -63.9656) -> (80.8551, -63.38)
  line L3300 (174.108, -60.8595) -> (174.402, -60.3542)
  line L3301 (187.99, -72.0008) -> (187.536, -72.3681)
  line L3302 (188.42, -71.6049) -> (187.99, -72.0008)
  line L3303 (174.402, -60.3542) -> (174.727, -59.869)
  line L3304 (173.622, -61.9215) -> (173.848, -61.3827)
  line L3305 (173.848, -61.3827) -> (174.108, -60.8595)
  line L3306 (168.218, -61.1969) -> (168.456, -61.7305)
  line L3307 (168.827, -62.8382) -> (168.957, -63.4077)
  line L3308 (168.659, -62.2784) -> (168.827, -62.8382)
  line L3309 (169.051, -63.9844) -> (169.108, -64.566)
  line L3310 (189.199, -70.7342) -> (188.823, -71.1821)
  line L3311 (188.823, -71.1821) -> (188.42, -71.6049)
  line L3312 (174.55, -70.001) -> (174.888, -70.4892)
  line L3313 (175.657, -71.3931) -> (176.085, -71.8049)
  line L3314 (175.257, -70.9539) -> (175.657, -71.3931)
  line L3315 (177.518, -72.8579) -> (178.039, -73.1431)
  line L3316 (176.085, -71.8049) -> (176.539, -72.1873)
  line L3317 (176.539, -72.1873) -> (177.018, -72.5389)
  line L3318 (163.128, -56.6297) -> (163.671, -56.8443)
  line L3319 (164.711, -57.3764) -> (165.203, -57.6917)
  line L3320 (164.199, -57.0936) -> (164.711, -57.3764)
  line L3321 (165.673, -58.038) -> (166.121, -58.414)
  line L3322 (177.018, -72.5389) -> (177.518, -72.8579)
  line L3323 (157.386, -56.5094) -> (157.949, -56.3538)
  line L3324 (178.578, -73.3931) -> (179.132, -73.6069)
  line L3325 (159.099, -56.1529) -> (159.682, -56.1086)
  line L3326 (159.452, -74.0832) -> (160.046, -74.1049)
  line L3327 (158.861, -74.0221) -> (159.452, -74.0832)
  line L3328 (76.4456, -57.333) -> (75.9179, -57.0606)
  line L3329 (160.046, -74.1049) -> (160.639, -74.0873)
  line L3330 (157.132, -73.6069) -> (157.699, -73.7835)
  line L3331 (162.395, -73.7999) -> (162.963, -73.6272)
  line L3332 (173.029, -65.3553) -> (173.033, -64.9312)
  line L3333 (73.8162, -73.9345) -> (74.3945, -73.7999)
  line L3334 (77.9045, -58.3507) -> (77.4411, -57.9794)
  line L3335 (77.4411, -57.9794) -> (76.954, -57.6397)
  line L3336 (74.3945, -73.7999) -> (74.9627, -73.6272)
  line L3337 (173.277, -63.0373) -> (173.432, -62.4738)
  line L3338 (81.0211, -65.5875) -> (81.0318, -65.15)
  line L3339 (173.432, -62.4738) -> (173.622, -61.9215)
  line L3340 (189.544, -70.263) -> (189.199, -70.7342)
  line L3341 (189.858, -69.7704) -> (189.544, -70.263)
  line L3342 (173.078, -64.1883) -> (173.159, -63.6096)
  line L3343 (173.159, -63.6096) -> (173.277, -63.0373)
  line L3344 (63.1245, -64.9312) -> (63.1297, -65.525)
  line L3345 (165.203, -57.6917) -> (165.673, -58.038)
  line L3346 (166.543, -58.818) -> (166.938, -59.2485)
  line L3347 (166.121, -58.414) -> (166.543, -58.818)
  line L3348 (167.304, -59.7036) -> (167.641, -60.1813)
  line L3349 (190.389, -68.7297) -> (190.14, -69.2586)
  line L3350 (190.14, -69.2586) -> (189.858, -69.7704)
  line L3351 (173.174, -66.1171) -> (173.258, -66.705)
  line L3352 (173.035, -64.771) -> (173.078, -64.1883)
  line L3353 (173.38, -67.2861) -> (173.541, -67.8577)
  line L3354 (173.541, -67.8577) -> (173.739, -68.4175)
  line L3355 (173.739, -68.4175) -> (173.974, -68.9629)
  line L3356 (173.258, -66.705) -> (173.38, -67.2861)
  line L3357 (159.682, -56.1086) -> (160.266, -56.102)
  line L3358 (161.43, -56.2018) -> (162.005, -56.3077)
  line L3359 (160.85, -56.1331) -> (161.43, -56.2018)
  line L3360 (162.571, -56.4506) -> (163.128, -56.6297)
  line L3361 (174.245, -69.4915) -> (174.55, -70.001)
  line L3362 (158.521, -56.2348) -> (159.099, -56.1529)
  line L3363 (173.974, -68.9629) -> (174.245, -69.4915)
  line L3364 (160.266, -56.102) -> (160.85, -56.1331)
  line L3365 (157.699, -73.7835) -> (158.276, -73.9221)
  line L3366 (156.578, -73.3931) -> (157.132, -73.6069)
  line L3367 (78.7525, -59.1812) -> (78.3423, -58.7519)
  line L3368 (156.039, -73.1431) -> (156.578, -73.3931)
  line L3369 (155.018, -72.5389) -> (155.518, -72.8579)
  line L3370 (158.276, -73.9221) -> (158.861, -74.0221)
  line L3371 (173.033, -64.9312) -> (173.035, -64.771)
  line L3372 (72.6391, -74.0873) -> (73.2302, -74.0304)
  line L3373 (78.3423, -58.7519) -> (77.9045, -58.3507)
  line L3374 (79.4833, -60.1165) -> (79.1334, -59.6368)
  line L3375 (73.2302, -74.0304) -> (73.8162, -73.9345)
  line L3376 (63.1297, -65.525) -> (63.1742, -66.1171)
  line L3377 (81.0318, -65.15) -> (81.0121, -64.5565)
  line L3378 (63.232, -63.7491) -> (63.1587, -64.3384)
  line L3379 (190.602, -68.1858) -> (190.389, -68.7297)
  line L3380 (190.781, -67.6293) -> (190.602, -68.1858)
  line L3381 (63.1587, -64.3384) -> (63.1245, -64.9312)
  line L3382 (63.495, -62.5917) -> (63.3443, -63.166)
  line L3383 (63.3443, -63.166) -> (63.232, -63.7491)
  line L3384 (162.005, -56.3077) -> (162.571, -56.4506)
  line L3385 (163.671, -56.8443) -> (164.199, -57.0936)
  line L3386 (132.085, -95.5049) -> (132.539, -95.8873)
  line L3387 (178.578, -97.0931) -> (179.132, -97.3069)
  line L3388 (80.1527, -92.7193) -> (80.3914, -92.1756)
  line L3389 (129.38, -90.9861) -> (129.541, -91.5577)
  line L3390 (143.565, -95.9258) -> (144.022, -95.5465)
  line L3391 (142.059, -96.8711) -> (142.581, -96.5896)
  line L3392 (191.027, -90.1877) -> (190.922, -90.7625)
  line L3393 (129.131, -90.2189) -> (129.061, -89.6388)
  line L3394 (144.856, -94.7014) -> (145.229, -94.2393)
  line L3395 (145.229, -94.2393) -> (145.57, -93.7534)
  line L3396 (145.57, -93.7534) -> (145.879, -93.246)
  line L3397 (174.795, -83.6371) -> (174.466, -84.1311)
  line L3398 (65.2572, -94.6539) -> (65.6569, -95.0931)
  line L3399 (188.121, -82.114) -> (188.543, -82.518)
  line L3400 (80.9224, -90.7625) -> (80.7806, -91.3293)
  line L3401 (180.123, -80.1107) -> (179.548, -80.2593)
  line L3402 (177.772, -80.8892) -> (178.295, -80.628)
  line L3403 (76.0585, -96.8711) -> (76.5813, -96.5896)
  line L3404 (173.777, -92.4587) -> (173.562, -91.9156)
  line L3405 (78.9379, -82.9485) -> (79.3045, -83.4036)
  line L3406 (188.453, -95.1378) -> (188.856, -94.7014)
  line L3407 (64.0276, -92.9867) -> (63.7774, -92.4587)
  line L3408 (63.1309, -90.2189) -> (63.0612, -89.6388)
  line L3409 (78.42, -95.3049) -> (77.9903, -95.7008)
  line L3410 (19.1589, -87.3096) -> (19.2769, -86.7373)
  line L3411 (135.699, -97.4835) -> (136.276, -97.6221)
  line L3412 (141.918, -80.7606) -> (141.373, -80.5239)
  line L3413 (173.382, -91.3597) -> (173.238, -90.7934)
  line L3414 (183.663, -80.0365) -> (183.075, -79.9508)
  line L3415 (190.885, -90.4665) -> (190.972, -89.8793)
  line L3416 (70.1233, -80.1107) -> (69.5484, -80.2593)
  line L3417 (134.578, -97.0931) -> (135.132, -97.3069)
  line L3418 (78.7525, -82.8812) -> (78.3423, -82.4519)
  line L3419 (176.539, -95.8873) -> (177.018, -96.2389)
  line L3420 (65.7561, -95.327) -> (65.3513, -94.9056)
  line L3421 (176.643, -96.0871) -> (176.187, -95.7214)
  line L3422 (81.0121, -88.2565) -> (80.9531, -87.6656)
  line L3423 (173.432, -86.1738) -> (173.622, -85.6215)
  line L3424 (181.296, -79.9291) -> (180.707, -80.0004)
  line L3425 (185.511, -97.2231) -> (184.963, -97.4273)
  line L3426 (63.6222, -85.6215) -> (63.8482, -85.0827)
  line L3427 (191.012, -88.2565) -> (190.953, -87.6656)
  line L3428 (67.3845, -81.2228) -> (66.8893, -81.5505)
  line L3429 (139.663, -80.0365) -> (139.075, -79.9508)
  line L3430 (137.296, -79.9291) -> (136.707, -80.0004)
  line L3431 (132.643, -96.0871) -> (132.187, -95.7214)
  line L3432 (67.7724, -80.8892) -> (68.2951, -80.628)
  line L3433 (143.084, -96.274) -> (143.565, -95.9258)
  line L3434 (63.1742, -89.8171) -> (63.2578, -90.405)
  line L3435 (64.402, -84.0542) -> (64.7274, -83.569)
  line L3436 (189.641, -83.8813) -> (189.946, -84.3798)
  line L3437 (76.1995, -80.7936) -> (76.7108, -81.0764)
  line L3438 (81.0274, -90.1877) -> (80.9224, -90.7625)
  line L3439 (174.402, -84.0542) -> (174.727, -83.569)
  line L3440 (179.78, -97.6038) -> (179.22, -97.4373)
  line L3441 (188.823, -94.8821) -> (188.42, -95.3049)
  line L3442 (78.3423, -82.4519) -> (77.9045, -82.0507)
  line L3443 (68.4345, -80.6692) -> (67.9003, -80.9286)
  line L3444 (173.232, -87.4491) -> (173.159, -88.0384)
  line L3445 (67.0175, -96.2389) -> (67.5183, -96.5579)
  line L3446 (180.276, -97.6221) -> (180.861, -97.7221)
  line L3447 (76.4456, -81.033) -> (75.9179, -80.7606)
  line L3448 (72.6766, -97.8801) -> (72.0926, -97.9)
  line L3449 (133.518, -96.5579) -> (134.039, -96.8431)
  line L3450 (70.2761, -97.6221) -> (70.8615, -97.7221)
  line L3451 (175.469, -82.6664) -> (175.882, -82.2528)
  line L3452 (144.342, -82.4519) -> (143.904, -82.0507)
  line L3453 (76.954, -81.3397) -> (76.4456, -81.033)
  line L3454 (66.643, -96.0871) -> (66.1873, -95.7214)
  line L3455 (73.8162, -97.6345) -> (74.3945, -97.4999)
  line L3456 (129.061, -89.6388) -> (129.029, -89.0553)
  line L3457 (79.2286, -94.2393) -> (79.57, -93.7534)
  line L3458 (133.385, -81.2228) -> (132.889, -81.5505)
  line L3459 (188.938, -82.9485) -> (189.304, -83.4036)
  line L3460 (63.1245, -88.6312) -> (63.1297, -89.225)
  line L3461 (141.373, -80.5239) -> (140.814, -80.3237)
  line L3462 (130.466, -84.1311) -> (130.17, -84.6459)
  line L3463 (146.594, -91.6172) -> (146.758, -91.0467)
  line L3464 (129.232, -87.4491) -> (129.159, -88.0384)
  line L3465 (173.974, -92.6629) -> (174.245, -93.1915)
  line L3466 (65.5489, -82.7199) -> (65.157, -83.166)
  line L3467 (139.23, -97.7304) -> (139.816, -97.6345)
  line L3468 (173.562, -91.9156) -> (173.382, -91.3597)
  line L3469 (74.4039, -97.5957) -> (73.8346, -97.7276)
  line L3470 (191.127, -88.85) -> (191.125, -89.0237)
  line L3471 (186.044, -96.9841) -> (185.511, -97.2231)
  line L3472 (182.677, -97.8801) -> (182.093, -97.9)
  line L3473 (147.012, -88.2565) -> (146.953, -87.6656)
  line L3474 (189.879, -93.246) -> (190.153, -92.7193)
  line L3475 (73.2302, -97.7304) -> (73.8162, -97.6345)
  line L3476 (173.683, -85.7285) -> (173.495, -86.2917)
  line L3477 (66.539, -95.8873) -> (67.0175, -96.2389)
  line L3478 (190.719, -86.5021) -> (190.544, -85.9345)
  line L3479 (131.549, -82.7199) -> (131.157, -83.166)
  line L3480 (146.758, -91.0467) -> (146.885, -90.4665)
  line L3481 (63.8482, -85.0827) -> (64.1085, -84.5595)
  line L3482 (178.672, -97.2351) -> (178.138, -96.9979)
  line L3483 (177.62, -96.7267) -> (177.121, -96.4227)
  line L3484 (134.039, -96.8431) -> (134.578, -97.0931)
  line L3485 (185.373, -80.5239) -> (184.814, -80.3237)
  line L3486 (146.391, -92.1756) -> (146.594, -91.6172)
  line L3487 (67.9003, -80.9286) -> (67.3845, -81.2228)
  line L3488 (141.518, -97.1173) -> (142.059, -96.8711)
  line L3489 (79.8785, -93.246) -> (80.1527, -92.7193)
  line L3490 (71.5085, -97.8821) -> (70.9269, -97.8266)
  line L3491 (63.541, -91.5577) -> (63.7392, -92.1175)
  line L3492 (134.985, -80.4458) -> (134.434, -80.6692)
  line L3493 (66.7829, -81.5099) -> (67.2676, -81.1835)
  line L3494 (175.351, -94.9056) -> (174.975, -94.459)
  line L3495 (184.571, -80.1506) -> (185.128, -80.3297)
  line L3496 (72.6391, -97.7873) -> (73.2302, -97.7304)
  line L3497 (190.602, -91.8858) -> (190.389, -92.4297)
  line L3498 (186.059, -96.8711) -> (186.581, -96.5896)
  line L3499 (174.55, -93.701) -> (174.888, -94.1892)
  line L3500 (173.238, -90.7934) -> (173.131, -90.2189)
  line L3501 (186.954, -81.3397) -> (186.446, -81.033)
  line L3502 (63.0291, -89.0553) -> (63.0332, -88.6312)
  line L3503 (187.536, -96.0681) -> (187.059, -96.4054)
  line L3504 (184.005, -80.0077) -> (184.571, -80.1506)
  line L3505 (173.159, -87.3096) -> (173.277, -86.7373)
  line L3506 (19.6222, -85.6215) -> (19.8482, -85.0827)
  line L3507 (182.266, -79.802) -> (182.85, -79.8331)
  line L3508 (177.518, -96.5579) -> (178.039, -96.8431)
  line L3509 (176.32, -81.8668) -> (176.783, -81.5099)
  line L3510 (175.549, -82.7199) -> (175.157, -83.166)
  line L3511 (70.9269, -97.8266) -> (70.35, -97.7337)
  line L3512 (189.858, -93.4704) -> (189.544, -93.963)
  line L3513 (146.153, -92.7193) -> (146.391, -92.1756)
  line L3514 (72.8498, -79.8331) -> (73.4301, -79.9018)
  line L3515 (183.075, -79.9508) -> (182.483, -79.9042)
  line L3516 (81.0514, -87.6844) -> (81.1079, -88.266)
  line L3517 (129.495, -86.2917) -> (129.344, -86.866)
  line L3518 (146.885, -90.4665) -> (146.972, -89.8793)
  line L3519 (73.4301, -79.9018) -> (74.0047, -80.0077)
  line L3520 (80.3887, -92.4297) -> (80.1404, -92.9586)
  line L3521 (187.673, -81.738) -> (188.121, -82.114)
  line L3522 (130.795, -83.6371) -> (130.466, -84.1311)
  line L3523 (173.124, -88.6312) -> (173.13, -89.225)
  line L3524 (173.033, -88.6312) -> (173.035, -88.471)
  line L3525 (78.0223, -95.5465) -> (78.453, -95.1378)
  line L3526 (173.622, -85.6215) -> (173.848, -85.0827)
  line L3527 (129.159, -88.0384) -> (129.124, -88.6312)
  line L3528 (77.5654, -95.9258) -> (78.0223, -95.5465)
  line L3529 (182.85, -79.8331) -> (183.43, -79.9018)
  line L3530 (81.1079, -88.266) -> (81.1268, -88.85)
  line L3531 (173.258, -90.405) -> (173.38, -90.9861)
  line L3532 (181.452, -97.7832) -> (182.046, -97.8049)
  line L3533 (80.5439, -85.9345) -> (80.3321, -85.3798)
  line L3534 (63.7392, -92.1175) -> (63.9741, -92.6629)
  line L3535 (129.344, -86.866) -> (129.232, -87.4491)
  line L3536 (144.753, -82.8812) -> (144.342, -82.4519)
  line L3537 (72.483, -79.9042) -> (71.8893, -79.897)
  line L3538 (76.7108, -81.0764) -> (77.2028, -81.3917)
  line L3539 (63.232, -87.4491) -> (63.1587, -88.0384)
  line L3540 (80.1404, -92.9586) -> (79.8585, -93.4704)
  line L3541 (131.97, -82.3007) -> (131.549, -82.7199)
  line L3542 (174.888, -94.1892) -> (175.257, -94.6539)
  line L3543 (186.711, -81.0764) -> (187.203, -81.3917)
  line L3544 (173.174, -89.8171) -> (173.258, -90.405)
  line L3545 (63.9741, -92.6629) -> (64.2446, -93.1915)
  line L3546 (63.078, -87.8883) -> (63.1589, -87.3096)
  line L3547 (77.2028, -81.3917) -> (77.6734, -81.738)
  line L3548 (63.2379, -90.7934) -> (63.1309, -90.2189)
  line L3549 (174.028, -92.9867) -> (173.777, -92.4587)
  line L3550 (74.5713, -80.1506) -> (75.1275, -80.3297)
  line L3551 (63.1589, -87.3096) -> (63.2769, -86.7373)
  line L3552 (19.078, -87.8883) -> (19.1589, -87.3096)
  line L3553 (180.861, -97.7221) -> (181.452, -97.7832)
  line L3554 (136.861, -97.7221) -> (137.452, -97.7832)
  line L3555 (136.276, -97.6221) -> (136.861, -97.7221)
  line L3556 (190.758, -91.0467) -> (190.885, -90.4665)
  line L3557 (66.417, -81.9104) -> (65.9695, -82.3007)
  line L3558 (178.295, -80.628) -> (178.834, -80.4011)
  line L3559 (173.277, -86.7373) -> (173.432, -86.1738)
  line L3560 (175.97, -82.3007) -> (175.549, -82.7199)
  line L3561 (131.157, -83.166) -> (130.795, -83.6371)
  line L3562 (190.389, -92.4297) -> (190.14, -92.9586)
  line L3563 (190.332, -85.3798) -> (190.084, -84.8403)
  line L3564 (64.6274, -93.989) -> (64.3113, -93.4975)
  line L3565 (135.132, -97.3069) -> (135.699, -97.4835)
  line L3566 (173.344, -86.866) -> (173.232, -87.4491)
  line L3567 (79.57, -93.7534) -> (79.8785, -93.246)
  line L3568 (140.963, -97.3272) -> (141.518, -97.1173)
  line L3569 (133.9, -80.9286) -> (133.385, -81.2228)
  line L3570 (63.4315, -86.1738) -> (63.6222, -85.6215)
  line L3571 (67.5183, -96.5579) -> (68.0392, -96.8431)
  line L3572 (75.5109, -97.2231) -> (74.9634, -97.4273)
  line L3573 (138.046, -97.8049) -> (138.639, -97.7873)
  line L3574 (81.1251, -89.0237) -> (81.0951, -89.6073)
  line L3575 (80.7582, -91.0467) -> (80.8847, -90.4665)
  line L3576 (175.257, -94.6539) -> (175.657, -95.0931)
  line L3577 (183.23, -97.7304) -> (183.816, -97.6345)
  line L3578 (79.5441, -93.963) -> (79.1986, -94.4342)
  line L3579 (133.121, -96.4227) -> (132.643, -96.0871)
  line L3580 (68.672, -97.2351) -> (68.138, -96.9979)
  line L3581 (69.2202, -97.4373) -> (68.672, -97.2351)
  line L3582 (146.332, -85.3798) -> (146.084, -84.8403)
  line L3583 (176.783, -81.5099) -> (177.268, -81.1835)
  line L3584 (190.218, -84.8969) -> (190.456, -85.4305)
  line L3585 (181.509, -97.8821) -> (180.927, -97.8266)
  line L3586 (134.434, -80.6692) -> (133.9, -80.9286)
  line L3587 (131.756, -95.327) -> (131.351, -94.9056)
  line L3588 (71.4521, -97.7832) -> (72.0455, -97.8049)
  line L3589 (174.627, -93.989) -> (174.311, -93.4975)
  line L3590 (66.8893, -81.5505) -> (66.417, -81.9104)
  line L3591 (189.946, -84.3798) -> (190.218, -84.8969)
  line L3592 (174.245, -93.1915) -> (174.55, -93.701)
  line L3593 (74.9627, -97.3272) -> (75.5182, -97.1173)
  line L3594 (66.3203, -81.8668) -> (66.7829, -81.5099)
  line L3595 (173.848, -85.0827) -> (174.108, -84.5595)
  line L3596 (179.699, -97.4835) -> (180.276, -97.6221)
  line L3597 (146.544, -85.9345) -> (146.332, -85.3798)
  line L3598 (146.953, -87.6656) -> (146.855, -87.08)
  line L3599 (68.138, -96.9979) -> (67.6204, -96.7267)
  line L3600 (68.0392, -96.8431) -> (68.5778, -97.0931)
  line L3601 (178.834, -80.4011) -> (179.386, -80.2094)
  line L3602 (173.078, -87.8883) -> (173.159, -87.3096)
  line L3603 (66.0847, -95.5049) -> (66.539, -95.8873)
  line L3604 (75.5182, -97.1173) -> (76.0585, -96.8711)
  line L3605 (174.727, -83.569) -> (175.084, -83.1057)
  line L3606 (81.0318, -88.85) -> (81.0121, -88.2565)
  line L3607 (80.2178, -84.8969) -> (80.4559, -85.4305)
  line L3608 (173.909, -85.1791) -> (173.683, -85.7285)
  line L3609 (180.35, -97.7337) -> (179.78, -97.6038)
  line L3610 (173.739, -92.1175) -> (173.974, -92.6629)
  line L3611 (63.2578, -90.405) -> (63.3803, -90.9861)
  line L3612 (77.6734, -81.738) -> (78.1207, -82.114)
  line L3613 (174.17, -84.6459) -> (173.909, -85.1791)
  line L3614 (73.2581, -97.8226) -> (72.6766, -97.8801)
  line L3615 (177.268, -81.1835) -> (177.772, -80.8892)